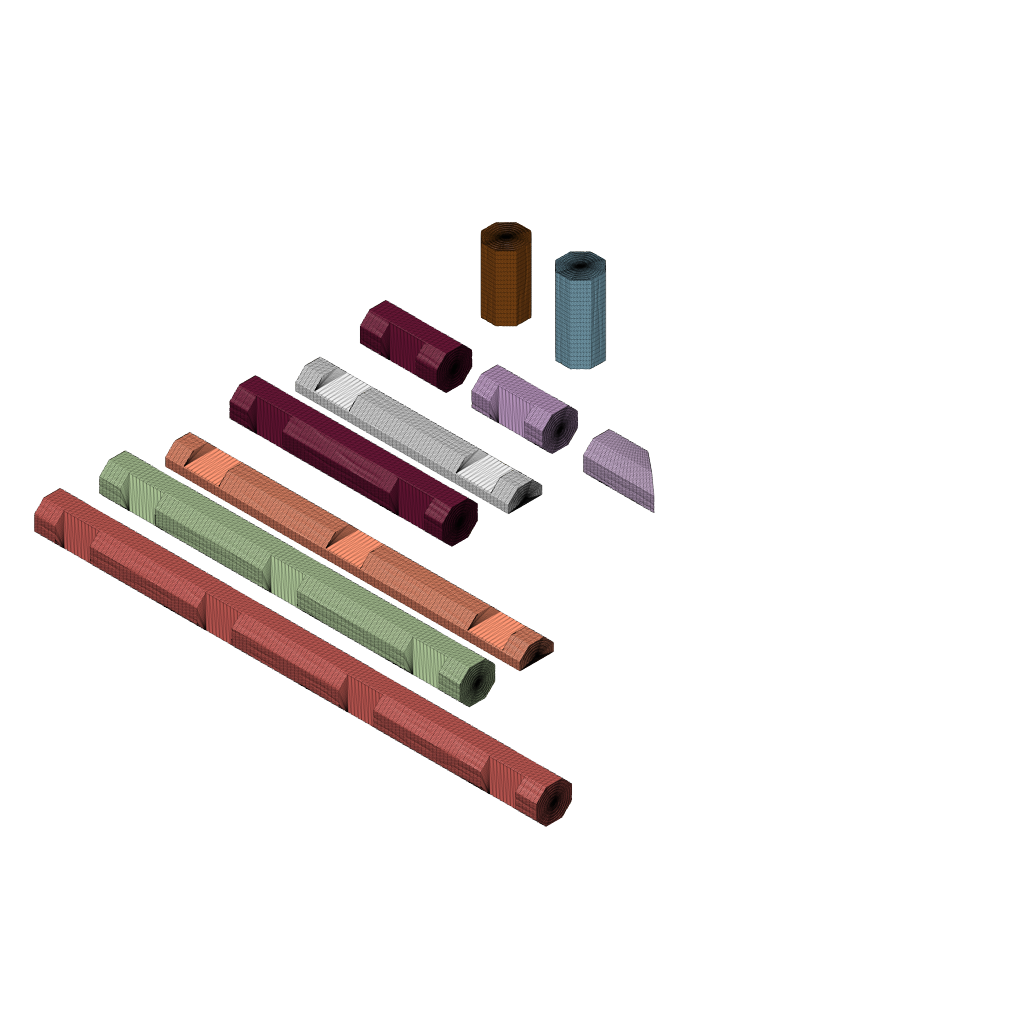
DeadPresidentTreeSections_flat_end_octagonal (Autodesk Fusion 360 design; units mm, degrees)
part number: 2026-11-17-20-53-10-812
part number: 2026-11-17-20-53-11-139
part number: 2026-11-17-20-53-11-399
part number: 2026-11-17-20-53-11-676
part number: 2026-11-17-20-53-11-946
part number: 2026-11-17-20-53-12-259
part number: 2026-11-17-20-53-12-647
part number: 2026-11-17-20-53-13-070
part number: 2026-11-17-20-53-13-551
part number: 2026-11-17-20-53-13-968
part number: 2026-11-17-20-53-14-124
Autodesk Fusion 360 part; units mm, degrees
sketch "Section" plane through (0, 0, 0) normal (1, 0, 0) x (0, 0, -1) in component "log_1insert_1-5_8_oct"
  line L0 (0.4, -9.525) -> (0.4, 9.525)
  line L1 (0.4, 9.525) -> (-18.65, 9.525)
  line L2 (-18.65, 9.525) -> (-18.65, -9.525)
  line L3 (-18.65, -9.525) -> (0.4, -9.525)
  dimension "d14" = 9.525
  dimension "d15" = 0.4
  dimension "d16" = 9.525
  dimension "d17" = 18.65
  constraint vertical L0
  constraint horizontal L1
  constraint vertical L2
  constraint horizontal L3
  measures "d14" vertical distance of origin L0.start
  measures "d15" horizontal distance of origin L0.start
  measures "d16" vertical distance of origin L1.end
  measures "d17" horizontal distance of origin L1.end
extrude "Log" add sketch "Section" along normal blind 41.275 makes body 1 in component "log_1insert_1-5_8_oct"
chamfer "Octagon corners" distance 5.5796 angle 45 4 edges at (20.6375, -9.525, 18.65) (20.6375, 9.525, 18.65) (20.6375, 9.525, -0.4) (20.6375, -9.525, -0.4) tangent chain off on bodies 1 in component "log_1insert_1-5_8_oct"
sketch "Flats" plane through (0, 0, 0) normal (1, 0, 0) x (0, 0, -1) in component "log_1insert_1-5_8_oct"
  line L0 (0.8, -11.525) -> (0.8, 11.525)
  line L1 (0.8, 11.525) -> (0, 11.525)
  line L2 (0, 11.525) -> (0, -11.525)
  line L3 (0, -11.525) -> (0.8, -11.525)
  line L4 (-18.25, -11.525) -> (-18.25, 11.525)
  line L5 (-18.25, 11.525) -> (-20.05, 11.525)
  line L6 (-20.05, 11.525) -> (-20.05, -11.525)
  line L7 (-20.05, -11.525) -> (-18.25, -11.525)
  dimension "d21" = 11.525
  dimension "d22" = 0.8
  dimension "d23" = 11.525
  dimension "d24" = 11.525
  dimension "d25" = 18.25
  dimension "d26" = 11.525
  dimension "d27" = 20.05
  constraint vertical L0
  constraint horizontal L1
  constraint vertical L2
  constraint horizontal L3
  constraint vertical origin L1.end
  constraint vertical L4
  constraint horizontal L5
  constraint vertical L6
  constraint horizontal L7
  measures "d21" vertical distance of origin L0.start
  measures "d22" horizontal distance of origin L0.start
  measures "d23" vertical distance of origin L1.end
  measures "d24" vertical distance of origin L4.start
  measures "d25" horizontal distance of origin L4.start
  measures "d26" vertical distance of origin L5.end
  measures "d27" horizontal distance of origin L5.end
extrude "Flats (1)" cut sketch "Flats" along normal blind 41.275 bodies 1 in component "log_1insert_1-5_8_oct"
sketch "Notch" plane through (0, 0, 0) normal (0, 0, 1) x (1, 0, 0) in component "log_1insert_1-5_8_oct"
  line L0 (11.3125, 4.7625) -> (29.9625, 4.7625)
  line L1 (29.9625, 4.7625) -> (29.9625, 11.525)
  line L2 (29.9625, 11.525) -> (11.3125, 11.525)
  line L3 (11.3125, 11.525) -> (11.3125, 4.7625)
  line L4 (11.3125, -4.7625) -> (29.9625, -4.7625)
  line L5 (29.9625, -4.7625) -> (29.9625, -11.525)
  line L6 (29.9625, -11.525) -> (11.3125, -11.525)
  line L7 (11.3125, -11.525) -> (11.3125, -4.7625)
  dimension "d30" = 11.3125
  dimension "d31" = 4.7625
  dimension "d32" = 29.9625
  dimension "d33" = 11.525
  dimension "d34" = 11.3125
  dimension "d35" = 4.7625
  dimension "d36" = 29.9625
  dimension "d37" = 11.525
  constraint horizontal L0
  constraint vertical L1
  constraint horizontal L2
  constraint vertical L3
  constraint horizontal L4
  constraint vertical L5
  constraint horizontal L6
  constraint vertical L7
  measures "d30" horizontal distance of origin L0.start
  measures "d31" vertical distance of origin L0.start
  measures "d32" horizontal distance of origin L1.end
  measures "d33" vertical distance of origin L1.end
  measures "d34" horizontal distance of origin L4.start
  measures "d35" vertical distance of origin L4.start
  measures "d36" horizontal distance of origin L5.end
  measures "d37" vertical distance of origin L5.end
extrude "Notch cut" cut sketch "Notch" along normal blind 21.05 bodies 1 in component "log_1insert_1-5_8_oct"
pattern_linear "Notch pattern" count 2 spacing 0.001 along (1, 0, 0) count 3 spacing 0 along (1, 0, 0) of "Notch cut" in component "log_1insert_1-5_8_oct"
other "Base Mesh Feature1" in component "log_1insert_1-5_8_oct"
sketch "Section (2)" plane through (0, 0, 0) normal (1, 0, 0) x (0, 0, -1) in component "log_1insert_1-1_2_oct"
  line L0 (0.4, -9.525) -> (0.4, 9.525)
  line L1 (0.4, 9.525) -> (-18.65, 9.525)
  line L2 (-18.65, 9.525) -> (-18.65, -9.525)
  line L3 (-18.65, -9.525) -> (0.4, -9.525)
  dimension "d48" = 9.525
  dimension "d49" = 0.4
  dimension "d50" = 9.525
  dimension "d51" = 18.65
  constraint vertical L0
  constraint horizontal L1
  constraint vertical L2
  constraint horizontal L3
  measures "d48" vertical distance of origin L0.start
  measures "d49" horizontal distance of origin L0.start
  measures "d50" vertical distance of origin L1.end
  measures "d51" horizontal distance of origin L1.end
extrude "Log'" add sketch "Section (2)" along normal blind 38.1 separate body makes body 2 in component "log_1insert_1-1_2_oct"
chamfer "Octagon corners'" distance 5.5796 angle 45 4 edges at (19.05, -9.525, 18.65) (19.05, 9.525, 18.65) (19.05, 9.525, -0.4) (19.05, -9.525, -0.4) tangent chain off on bodies 2 in component "log_1insert_1-1_2_oct"
sketch "Flats (2)" plane through (0, 0, 0) normal (1, 0, 0) x (0, 0, -1) in component "log_1insert_1-1_2_oct"
  line L0 (0.8, -11.525) -> (0.8, 11.525)
  line L1 (0.8, 11.525) -> (0, 11.525)
  line L2 (0, 11.525) -> (0, -11.525)
  line L3 (0, -11.525) -> (0.8, -11.525)
  line L4 (-18.25, -11.525) -> (-18.25, 11.525)
  line L5 (-18.25, 11.525) -> (-20.05, 11.525)
  line L6 (-20.05, 11.525) -> (-20.05, -11.525)
  line L7 (-20.05, -11.525) -> (-18.25, -11.525)
  dimension "d55" = 11.525
  dimension "d56" = 0.8
  dimension "d57" = 11.525
  dimension "d58" = 11.525
  dimension "d59" = 18.25
  dimension "d60" = 11.525
  dimension "d61" = 20.05
  constraint vertical L0
  constraint horizontal L1
  constraint vertical L2
  constraint horizontal L3
  constraint vertical origin L1.end
  constraint vertical L4
  constraint horizontal L5
  constraint vertical L6
  constraint horizontal L7
  measures "d55" vertical distance of origin L0.start
  measures "d56" horizontal distance of origin L0.start
  measures "d57" vertical distance of origin L1.end
  measures "d58" vertical distance of origin L4.start
  measures "d59" horizontal distance of origin L4.start
  measures "d60" vertical distance of origin L5.end
  measures "d61" horizontal distance of origin L5.end
extrude "Flats (1)'" cut sketch "Flats (2)" along normal blind 38.1 bodies 2 in component "log_1insert_1-1_2_oct"
sketch "Notch (2)" plane through (0, 0, 0) normal (0, 0, 1) x (1, 0, 0) in component "log_1insert_1-1_2_oct"
  line L0 (9.725, 4.7625) -> (28.375, 4.7625)
  line L1 (28.375, 4.7625) -> (28.375, 11.525)
  line L2 (28.375, 11.525) -> (9.725, 11.525)
  line L3 (9.725, 11.525) -> (9.725, 4.7625)
  line L4 (9.725, -4.7625) -> (28.375, -4.7625)
  line L5 (28.375, -4.7625) -> (28.375, -11.525)
  line L6 (28.375, -11.525) -> (9.725, -11.525)
  line L7 (9.725, -11.525) -> (9.725, -4.7625)
  dimension "d64" = 9.725
  dimension "d65" = 4.7625
  dimension "d66" = 28.375
  dimension "d67" = 11.525
  dimension "d68" = 9.725
  dimension "d69" = 4.7625
  dimension "d70" = 28.375
  dimension "d71" = 11.525
  constraint horizontal L0
  constraint vertical L1
  constraint horizontal L2
  constraint vertical L3
  constraint horizontal L4
  constraint vertical L5
  constraint horizontal L6
  constraint vertical L7
  measures "d64" horizontal distance of origin L0.start
  measures "d65" vertical distance of origin L0.start
  measures "d66" horizontal distance of origin L1.end
  measures "d67" vertical distance of origin L1.end
  measures "d68" horizontal distance of origin L4.start
  measures "d69" vertical distance of origin L4.start
  measures "d70" horizontal distance of origin L5.end
  measures "d71" vertical distance of origin L5.end
extrude "Notch cut'" cut sketch "Notch (2)" along normal blind 21.05 bodies 2 in component "log_1insert_1-1_2_oct"
pattern_linear "Notch pattern'" count 2 spacing 0.001 along (1, 0, 0) count 3 spacing 0 along (1, 0, 0) of "Notch cut'" in component "log_1insert_1-1_2_oct"
other "Base Mesh Feature1'" in component "log_1insert_1-1_2_oct"
sketch "Section (3)" plane through (0, 0, 0) normal (1, 0, 0) x (0, 0, -1) in component "log_2insert_4-1_2_oct"
  line L0 (0.4, -9.525) -> (0.4, 9.525)
  line L1 (0.4, 9.525) -> (-18.65, 9.525)
  line L2 (-18.65, 9.525) -> (-18.65, -9.525)
  line L3 (-18.65, -9.525) -> (0.4, -9.525)
  dimension "d82" = 9.525
  dimension "d83" = 0.4
  dimension "d84" = 9.525
  dimension "d85" = 18.65
  constraint vertical L0
  constraint horizontal L1
  constraint vertical L2
  constraint horizontal L3
  measures "d82" vertical distance of origin L0.start
  measures "d83" horizontal distance of origin L0.start
  measures "d84" vertical distance of origin L1.end
  measures "d85" horizontal distance of origin L1.end
extrude "Log''" add sketch "Section (3)" along normal blind 114.3 separate body makes body 3 in component "log_2insert_4-1_2_oct"
chamfer "Octagon corners''" distance 5.5796 angle 45 4 edges at (57.15, -9.525, 18.65) (57.15, 9.525, 18.65) (57.15, 9.525, -0.4) (57.15, -9.525, -0.4) tangent chain off on bodies 3 in component "log_2insert_4-1_2_oct"
sketch "Flats (3)" plane through (0, 0, 0) normal (1, 0, 0) x (0, 0, -1) in component "log_2insert_4-1_2_oct"
  line L0 (0.8, -11.525) -> (0.8, 11.525)
  line L1 (0.8, 11.525) -> (0, 11.525)
  line L2 (0, 11.525) -> (0, -11.525)
  line L3 (0, -11.525) -> (0.8, -11.525)
  line L4 (-18.25, -11.525) -> (-18.25, 11.525)
  line L5 (-18.25, 11.525) -> (-20.05, 11.525)
  line L6 (-20.05, 11.525) -> (-20.05, -11.525)
  line L7 (-20.05, -11.525) -> (-18.25, -11.525)
  dimension "d89" = 11.525
  dimension "d90" = 0.8
  dimension "d91" = 11.525
  dimension "d92" = 11.525
  dimension "d93" = 18.25
  dimension "d94" = 11.525
  dimension "d95" = 20.05
  constraint vertical L0
  constraint horizontal L1
  constraint vertical L2
  constraint horizontal L3
  constraint vertical origin L1.end
  constraint vertical L4
  constraint horizontal L5
  constraint vertical L6
  constraint horizontal L7
  measures "d89" vertical distance of origin L0.start
  measures "d90" horizontal distance of origin L0.start
  measures "d91" vertical distance of origin L1.end
  measures "d92" vertical distance of origin L4.start
  measures "d93" horizontal distance of origin L4.start
  measures "d94" vertical distance of origin L5.end
  measures "d95" horizontal distance of origin L5.end
extrude "Flats (1)''" cut sketch "Flats (3)" along normal blind 114.3 bodies 3 in component "log_2insert_4-1_2_oct"
sketch "Notch (3)" plane through (0, 0, 0) normal (0, 0, 1) x (1, 0, 0) in component "log_2insert_4-1_2_oct"
  line L0 (9.725, 4.7625) -> (28.375, 4.7625)
  line L1 (28.375, 4.7625) -> (28.375, 11.525)
  line L2 (28.375, 11.525) -> (9.725, 11.525)
  line L3 (9.725, 11.525) -> (9.725, 4.7625)
  line L4 (9.725, -4.7625) -> (28.375, -4.7625)
  line L5 (28.375, -4.7625) -> (28.375, -11.525)
  line L6 (28.375, -11.525) -> (9.725, -11.525)
  line L7 (9.725, -11.525) -> (9.725, -4.7625)
  dimension "d98" = 9.725
  dimension "d99" = 4.7625
  dimension "d100" = 28.375
  dimension "d101" = 11.525
  dimension "d102" = 9.725
  dimension "d103" = 4.7625
  dimension "d104" = 28.375
  dimension "d105" = 11.525
  constraint horizontal L0
  constraint vertical L1
  constraint horizontal L2
  constraint vertical L3
  constraint horizontal L4
  constraint vertical L5
  constraint horizontal L6
  constraint vertical L7
  measures "d98" horizontal distance of origin L0.start
  measures "d99" vertical distance of origin L0.start
  measures "d100" horizontal distance of origin L1.end
  measures "d101" vertical distance of origin L1.end
  measures "d102" horizontal distance of origin L4.start
  measures "d103" vertical distance of origin L4.start
  measures "d104" horizontal distance of origin L5.end
  measures "d105" vertical distance of origin L5.end
extrude "Notch cut''" cut sketch "Notch (3)" along normal blind 21.05 bodies 3 in component "log_2insert_4-1_2_oct"
pattern_linear "Notch pattern''" count 2 spacing 76.2 along (1, 0, 0) count 3 spacing 0 along (1, 0, 0) of "Notch cut''" in component "log_2insert_4-1_2_oct"
other "Base Mesh Feature1''" in component "log_2insert_4-1_2_oct"
sketch "Section (4)" plane through (0, 0, 0) normal (1, 0, 0) x (0, 0, -1) in component "log_3insert_7-5_8_oct"
  line L0 (0.4, -9.525) -> (0.4, 9.525)
  line L1 (0.4, 9.525) -> (-18.65, 9.525)
  line L2 (-18.65, 9.525) -> (-18.65, -9.525)
  line L3 (-18.65, -9.525) -> (0.4, -9.525)
  dimension "d116" = 9.525
  dimension "d117" = 0.4
  dimension "d118" = 9.525
  dimension "d119" = 18.65
  constraint vertical L0
  constraint horizontal L1
  constraint vertical L2
  constraint horizontal L3
  measures "d116" vertical distance of origin L0.start
  measures "d117" horizontal distance of origin L0.start
  measures "d118" vertical distance of origin L1.end
  measures "d119" horizontal distance of origin L1.end
extrude "Log'''" add sketch "Section (4)" along normal blind 193.675 separate body makes body 4 in component "log_3insert_7-5_8_oct"
chamfer "Octagon corners'''" distance 5.5796 angle 45 4 edges at (96.8375, -9.525, 18.65) (96.8375, 9.525, 18.65) (96.8375, 9.525, -0.4) (96.8375, -9.525, -0.4) tangent chain off on bodies 4 in component "log_3insert_7-5_8_oct"
sketch "Flats (4)" plane through (0, 0, 0) normal (1, 0, 0) x (0, 0, -1) in component "log_3insert_7-5_8_oct"
  line L0 (0.8, -11.525) -> (0.8, 11.525)
  line L1 (0.8, 11.525) -> (0, 11.525)
  line L2 (0, 11.525) -> (0, -11.525)
  line L3 (0, -11.525) -> (0.8, -11.525)
  line L4 (-18.25, -11.525) -> (-18.25, 11.525)
  line L5 (-18.25, 11.525) -> (-20.05, 11.525)
  line L6 (-20.05, 11.525) -> (-20.05, -11.525)
  line L7 (-20.05, -11.525) -> (-18.25, -11.525)
  dimension "d123" = 11.525
  dimension "d124" = 0.8
  dimension "d125" = 11.525
  dimension "d126" = 11.525
  dimension "d127" = 18.25
  dimension "d128" = 11.525
  dimension "d129" = 20.05
  constraint vertical L0
  constraint horizontal L1
  constraint vertical L2
  constraint horizontal L3
  constraint vertical origin L1.end
  constraint vertical L4
  constraint horizontal L5
  constraint vertical L6
  constraint horizontal L7
  measures "d123" vertical distance of origin L0.start
  measures "d124" horizontal distance of origin L0.start
  measures "d125" vertical distance of origin L1.end
  measures "d126" vertical distance of origin L4.start
  measures "d127" horizontal distance of origin L4.start
  measures "d128" vertical distance of origin L5.end
  measures "d129" horizontal distance of origin L5.end
extrude "Flats (1)'''" cut sketch "Flats (4)" along normal blind 193.675 bodies 4 in component "log_3insert_7-5_8_oct"
sketch "Notch (4)" plane through (0, 0, 0) normal (0, 0, 1) x (1, 0, 0) in component "log_3insert_7-5_8_oct"
  line L0 (11.3125, 4.7625) -> (29.9625, 4.7625)
  line L1 (29.9625, 4.7625) -> (29.9625, 11.525)
  line L2 (29.9625, 11.525) -> (11.3125, 11.525)
  line L3 (11.3125, 11.525) -> (11.3125, 4.7625)
  line L4 (11.3125, -4.7625) -> (29.9625, -4.7625)
  line L5 (29.9625, -4.7625) -> (29.9625, -11.525)
  line L6 (29.9625, -11.525) -> (11.3125, -11.525)
  line L7 (11.3125, -11.525) -> (11.3125, -4.7625)
  dimension "d132" = 11.3125
  dimension "d133" = 4.7625
  dimension "d134" = 29.9625
  dimension "d135" = 11.525
  dimension "d136" = 11.3125
  dimension "d137" = 4.7625
  dimension "d138" = 29.9625
  dimension "d139" = 11.525
  constraint horizontal L0
  constraint vertical L1
  constraint horizontal L2
  constraint vertical L3
  constraint horizontal L4
  constraint vertical L5
  constraint horizontal L6
  constraint vertical L7
  measures "d132" horizontal distance of origin L0.start
  measures "d133" vertical distance of origin L0.start
  measures "d134" horizontal distance of origin L1.end
  measures "d135" vertical distance of origin L1.end
  measures "d136" horizontal distance of origin L4.start
  measures "d137" vertical distance of origin L4.start
  measures "d138" horizontal distance of origin L5.end
  measures "d139" vertical distance of origin L5.end
extrude "Notch cut'''" cut sketch "Notch (4)" along normal blind 21.05 bodies 4 in component "log_3insert_7-5_8_oct"
pattern_linear "Notch pattern'''" count 3 spacing 76.2 along (1, 0, 0) count 3 spacing 0 along (1, 0, 0) of "Notch cut'''" in component "log_3insert_7-5_8_oct"
other "Base Mesh Feature1'''" in component "log_3insert_7-5_8_oct"
sketch "Section (5)" plane through (0, 0, 0) normal (1, 0, 0) x (0, 0, -1) in component "log_4insert_10-5_8_oct"
  line L0 (0.4, -9.525) -> (0.4, 9.525)
  line L1 (0.4, 9.525) -> (-18.65, 9.525)
  line L2 (-18.65, 9.525) -> (-18.65, -9.525)
  line L3 (-18.65, -9.525) -> (0.4, -9.525)
  dimension "d150" = 9.525
  dimension "d151" = 0.4
  dimension "d152" = 9.525
  dimension "d153" = 18.65
  constraint vertical L0
  constraint horizontal L1
  constraint vertical L2
  constraint horizontal L3
  measures "d150" vertical distance of origin L0.start
  measures "d151" horizontal distance of origin L0.start
  measures "d152" vertical distance of origin L1.end
  measures "d153" horizontal distance of origin L1.end
extrude "Log''''" add sketch "Section (5)" along normal blind 269.875 separate body makes body 5 in component "log_4insert_10-5_8_oct"
chamfer "Octagon corners''''" distance 5.5796 angle 45 4 edges at (134.9375, -9.525, 18.65) (134.9375, 9.525, 18.65) (134.9375, 9.525, -0.4) (134.9375, -9.525, -0.4) tangent chain off on bodies 5 in component "log_4insert_10-5_8_oct"
sketch "Flats (5)" plane through (0, 0, 0) normal (1, 0, 0) x (0, 0, -1) in component "log_4insert_10-5_8_oct"
  line L0 (0.8, -11.525) -> (0.8, 11.525)
  line L1 (0.8, 11.525) -> (0, 11.525)
  line L2 (0, 11.525) -> (0, -11.525)
  line L3 (0, -11.525) -> (0.8, -11.525)
  line L4 (-18.25, -11.525) -> (-18.25, 11.525)
  line L5 (-18.25, 11.525) -> (-20.05, 11.525)
  line L6 (-20.05, 11.525) -> (-20.05, -11.525)
  line L7 (-20.05, -11.525) -> (-18.25, -11.525)
  dimension "d157" = 11.525
  dimension "d158" = 0.8
  dimension "d159" = 11.525
  dimension "d160" = 11.525
  dimension "d161" = 18.25
  dimension "d162" = 11.525
  dimension "d163" = 20.05
  constraint vertical L0
  constraint horizontal L1
  constraint vertical L2
  constraint horizontal L3
  constraint vertical origin L1.end
  constraint vertical L4
  constraint horizontal L5
  constraint vertical L6
  constraint horizontal L7
  measures "d157" vertical distance of origin L0.start
  measures "d158" horizontal distance of origin L0.start
  measures "d159" vertical distance of origin L1.end
  measures "d160" vertical distance of origin L4.start
  measures "d161" horizontal distance of origin L4.start
  measures "d162" vertical distance of origin L5.end
  measures "d163" horizontal distance of origin L5.end
extrude "Flats (1)''''" cut sketch "Flats (5)" along normal blind 269.875 bodies 5 in component "log_4insert_10-5_8_oct"
sketch "Notch (5)" plane through (0, 0, 0) normal (0, 0, 1) x (1, 0, 0) in component "log_4insert_10-5_8_oct"
  line L0 (11.3125, 4.7625) -> (29.9625, 4.7625)
  line L1 (29.9625, 4.7625) -> (29.9625, 11.525)
  line L2 (29.9625, 11.525) -> (11.3125, 11.525)
  line L3 (11.3125, 11.525) -> (11.3125, 4.7625)
  line L4 (11.3125, -4.7625) -> (29.9625, -4.7625)
  line L5 (29.9625, -4.7625) -> (29.9625, -11.525)
  line L6 (29.9625, -11.525) -> (11.3125, -11.525)
  line L7 (11.3125, -11.525) -> (11.3125, -4.7625)
  dimension "d166" = 11.3125
  dimension "d167" = 4.7625
  dimension "d168" = 29.9625
  dimension "d169" = 11.525
  dimension "d170" = 11.3125
  dimension "d171" = 4.7625
  dimension "d172" = 29.9625
  dimension "d173" = 11.525
  constraint horizontal L0
  constraint vertical L1
  constraint horizontal L2
  constraint vertical L3
  constraint horizontal L4
  constraint vertical L5
  constraint horizontal L6
  constraint vertical L7
  measures "d166" horizontal distance of origin L0.start
  measures "d167" vertical distance of origin L0.start
  measures "d168" horizontal distance of origin L1.end
  measures "d169" vertical distance of origin L1.end
  measures "d170" horizontal distance of origin L4.start
  measures "d171" vertical distance of origin L4.start
  measures "d172" horizontal distance of origin L5.end
  measures "d173" vertical distance of origin L5.end
extrude "Notch cut''''" cut sketch "Notch (5)" along normal blind 21.05 bodies 5 in component "log_4insert_10-5_8_oct"
pattern_linear "Notch pattern''''" count 4 spacing 76.2 along (1, 0, 0) count 3 spacing 0 along (1, 0, 0) of "Notch cut''''" in component "log_4insert_10-5_8_oct"
other "Base Mesh Feature1''''" in component "log_4insert_10-5_8_oct"
sketch "Section (6)" plane through (0, 0, 0) normal (1, 0, 0) x (0, 0, -1) in component "base_log_4-1_2_oct"
  line L0 (9.525, -9.525) -> (9.525, 9.525)
  line L1 (9.525, 9.525) -> (-9.525, 9.525)
  line L2 (-9.525, 9.525) -> (-9.525, -9.525)
  line L3 (-9.525, -9.525) -> (9.525, -9.525)
  dimension "d184" = 9.525
  dimension "d185" = 9.525
  dimension "d186" = 9.525
  dimension "d187" = 9.525
  constraint vertical L0
  constraint horizontal L1
  constraint vertical L2
  constraint horizontal L3
  measures "d184" vertical distance of origin L0.start
  measures "d185" horizontal distance of origin L0.start
  measures "d186" vertical distance of origin L1.end
  measures "d187" horizontal distance of origin L1.end
extrude "Log'''''" add sketch "Section (6)" along normal blind 114.3 separate body makes body 6 in component "base_log_4-1_2_oct"
chamfer "Octagon corners'''''" distance 5.5796 angle 45 4 edges at (57.15, -9.525, 9.525) (57.15, 9.525, 9.525) (57.15, 9.525, -9.525) (57.15, -9.525, -9.525) tangent chain off on bodies 6 in component "base_log_4-1_2_oct"
sketch "Bed and side flats" plane through (0, 0, 0) normal (1, 0, 0) x (0, 0, -1) in component "base_log_4-1_2_oct"
  line L0 (10.525, -11.525) -> (10.525, 11.525)
  line L1 (10.525, 11.525) -> (0, 11.525)
  line L2 (0, 11.525) -> (0, -11.525)
  line L3 (0, -11.525) -> (10.525, -11.525)
  line L4 (1, 9.125) -> (1, 11.525)
  line L5 (1, 11.525) -> (-20.05, 11.525)
  line L6 (-20.05, 11.525) -> (-20.05, 9.125)
  line L7 (-20.05, 9.125) -> (1, 9.125)
  line L8 (1, -9.125) -> (1, -11.525)
  line L9 (1, -11.525) -> (-20.05, -11.525)
  line L10 (-20.05, -11.525) -> (-20.05, -9.125)
  line L11 (-20.05, -9.125) -> (1, -9.125)
  dimension "d191" = 11.525
  dimension "d192" = 10.525
  dimension "d193" = 11.525
  dimension "d194" = 9.125
  dimension "d195" = 1
  dimension "d196" = 11.525
  dimension "d197" = 20.05
  dimension "d198" = 9.125
  dimension "d199" = 1
  dimension "d200" = 11.525
  dimension "d201" = 20.05
  constraint vertical L0
  constraint horizontal L1
  constraint vertical L2
  constraint horizontal L3
  constraint vertical origin L1.end
  constraint vertical L4
  constraint horizontal L5
  constraint vertical L6
  constraint horizontal L7
  constraint vertical L8
  constraint horizontal L9
  constraint vertical L10
  constraint horizontal L11
  measures "d191" vertical distance of origin L0.start
  measures "d192" horizontal distance of origin L0.start
  measures "d193" vertical distance of origin L1.end
  measures "d194" vertical distance of origin L4.start
  measures "d195" horizontal distance of origin L4.start
  measures "d196" vertical distance of origin L5.end
  measures "d197" horizontal distance of origin L5.end
  measures "d198" vertical distance of origin L8.start
  measures "d199" horizontal distance of origin L8.start
  measures "d200" vertical distance of origin L9.end
  measures "d201" horizontal distance of origin L9.end
extrude "Bed and side flats (1)" cut sketch "Bed and side flats" along normal blind 114.3 bodies 6 in component "base_log_4-1_2_oct"
sketch "Notch (6)" plane through (0, 0, 0) normal (0, 1, 0) x (1, 0, 0) in component "base_log_4-1_2_oct"
  line L0 (9.725, -4.7625) -> (28.375, -4.7625)
  line L1 (28.375, -4.7625) -> (28.375, -10.525)
  line L2 (28.375, -10.525) -> (9.725, -10.525)
  line L3 (9.725, -10.525) -> (9.725, -4.7625)
  dimension "d204" = 9.725
  dimension "d205" = 4.7625
  dimension "d206" = 28.375
  dimension "d207" = 10.525
  constraint horizontal L0
  constraint vertical L1
  constraint horizontal L2
  constraint vertical L3
  measures "d204" horizontal distance of origin L0.start
  measures "d205" vertical distance of origin L0.start
  measures "d206" horizontal distance of origin L1.end
  measures "d207" vertical distance of origin L1.end
extrude "Notch cut'''''" cut sketch "Notch (6)" along normal mid plane 21.05 bodies 6 in component "base_log_4-1_2_oct"
pattern_linear "Notch pattern'''''" count 2 spacing 76.2 along (1, 0, 0) count 3 spacing 0 along (1, 0, 0) of "Notch cut'''''" in component "base_log_4-1_2_oct"
other "Base Mesh Feature1'''''" in component "base_log_4-1_2_oct"
sketch "Section (7)" plane through (0, 0, 0) normal (1, 0, 0) x (0, 0, -1) in component "base_log_7-1_2_oct"
  line L0 (9.525, -9.525) -> (9.525, 9.525)
  line L1 (9.525, 9.525) -> (-9.525, 9.525)
  line L2 (-9.525, 9.525) -> (-9.525, -9.525)
  line L3 (-9.525, -9.525) -> (9.525, -9.525)
  dimension "d218" = 9.525
  dimension "d219" = 9.525
  dimension "d220" = 9.525
  dimension "d221" = 9.525
  constraint vertical L0
  constraint horizontal L1
  constraint vertical L2
  constraint horizontal L3
  measures "d218" vertical distance of origin L0.start
  measures "d219" horizontal distance of origin L0.start
  measures "d220" vertical distance of origin L1.end
  measures "d221" horizontal distance of origin L1.end
extrude "Log''''''" add sketch "Section (7)" along normal blind 190.5 separate body makes body 7 in component "base_log_7-1_2_oct"
chamfer "Octagon corners''''''" distance 5.5796 angle 45 4 edges at (95.25, -9.525, 9.525) (95.25, 9.525, 9.525) (95.25, 9.525, -9.525) (95.25, -9.525, -9.525) tangent chain off on bodies 7 in component "base_log_7-1_2_oct"
sketch "Bed and side flats (2)" plane through (0, 0, 0) normal (1, 0, 0) x (0, 0, -1) in component "base_log_7-1_2_oct"
  line L0 (10.525, -11.525) -> (10.525, 11.525)
  line L1 (10.525, 11.525) -> (0, 11.525)
  line L2 (0, 11.525) -> (0, -11.525)
  line L3 (0, -11.525) -> (10.525, -11.525)
  line L4 (1, 9.125) -> (1, 11.525)
  line L5 (1, 11.525) -> (-20.05, 11.525)
  line L6 (-20.05, 11.525) -> (-20.05, 9.125)
  line L7 (-20.05, 9.125) -> (1, 9.125)
  line L8 (1, -9.125) -> (1, -11.525)
  line L9 (1, -11.525) -> (-20.05, -11.525)
  line L10 (-20.05, -11.525) -> (-20.05, -9.125)
  line L11 (-20.05, -9.125) -> (1, -9.125)
  dimension "d225" = 11.525
  dimension "d226" = 10.525
  dimension "d227" = 11.525
  dimension "d228" = 9.125
  dimension "d229" = 1
  dimension "d230" = 11.525
  dimension "d231" = 20.05
  dimension "d232" = 9.125
  dimension "d233" = 1
  dimension "d234" = 11.525
  dimension "d235" = 20.05
  constraint vertical L0
  constraint horizontal L1
  constraint vertical L2
  constraint horizontal L3
  constraint vertical origin L1.end
  constraint vertical L4
  constraint horizontal L5
  constraint vertical L6
  constraint horizontal L7
  constraint vertical L8
  constraint horizontal L9
  constraint vertical L10
  constraint horizontal L11
  measures "d225" vertical distance of origin L0.start
  measures "d226" horizontal distance of origin L0.start
  measures "d227" vertical distance of origin L1.end
  measures "d228" vertical distance of origin L4.start
  measures "d229" horizontal distance of origin L4.start
  measures "d230" vertical distance of origin L5.end
  measures "d231" horizontal distance of origin L5.end
  measures "d232" vertical distance of origin L8.start
  measures "d233" horizontal distance of origin L8.start
  measures "d234" vertical distance of origin L9.end
  measures "d235" horizontal distance of origin L9.end
extrude "Bed and side flats (1)'" cut sketch "Bed and side flats (2)" along normal blind 190.5 bodies 7 in component "base_log_7-1_2_oct"
sketch "Notch (7)" plane through (0, 0, 0) normal (0, 1, 0) x (1, 0, 0) in component "base_log_7-1_2_oct"
  line L0 (9.725, -4.7625) -> (28.375, -4.7625)
  line L1 (28.375, -4.7625) -> (28.375, -10.525)
  line L2 (28.375, -10.525) -> (9.725, -10.525)
  line L3 (9.725, -10.525) -> (9.725, -4.7625)
  dimension "d238" = 9.725
  dimension "d239" = 4.7625
  dimension "d240" = 28.375
  dimension "d241" = 10.525
  constraint horizontal L0
  constraint vertical L1
  constraint horizontal L2
  constraint vertical L3
  measures "d238" horizontal distance of origin L0.start
  measures "d239" vertical distance of origin L0.start
  measures "d240" horizontal distance of origin L1.end
  measures "d241" vertical distance of origin L1.end
extrude "Notch cut''''''" cut sketch "Notch (7)" along normal mid plane 21.05 bodies 7 in component "base_log_7-1_2_oct"
pattern_linear "Notch pattern''''''" count 3 spacing 76.2 along (1, 0, 0) count 3 spacing 0 along (1, 0, 0) of "Notch cut''''''" in component "base_log_7-1_2_oct"
other "Base Mesh Feature1''''''" in component "base_log_7-1_2_oct"
sketch "Section (8)" plane through (0, 0, 0) normal (1, 0, 0) x (0, 0, -1) in component "beveled_end_1-1_2_oct"
  line L0 (0.4, -9.525) -> (0.4, 9.525)
  line L1 (0.4, 9.525) -> (-18.65, 9.525)
  line L2 (-18.65, 9.525) -> (-18.65, -9.525)
  line L3 (-18.65, -9.525) -> (0.4, -9.525)
  dimension "d250" = 9.525
  dimension "d251" = 0.4
  dimension "d252" = 9.525
  dimension "d253" = 18.65
  constraint vertical L0
  constraint horizontal L1
  constraint vertical L2
  constraint horizontal L3
  measures "d250" vertical distance of origin L0.start
  measures "d251" horizontal distance of origin L0.start
  measures "d252" vertical distance of origin L1.end
  measures "d253" horizontal distance of origin L1.end
extrude "Log'''''''" add sketch "Section (8)" along normal blind 38.1 separate body makes body 8 in component "beveled_end_1-1_2_oct"
chamfer "Octagon corners'''''''" distance 5.5796 angle 45 4 edges at (19.05, -9.525, 18.65) (19.05, 9.525, 18.65) (19.05, 9.525, -0.4) (19.05, -9.525, -0.4) tangent chain off on bodies 8 in component "beveled_end_1-1_2_oct"
sketch "Flats (6)" plane through (0, 0, 0) normal (1, 0, 0) x (0, 0, -1) in component "beveled_end_1-1_2_oct"
  line L0 (0.8, -11.525) -> (0.8, 11.525)
  line L1 (0.8, 11.525) -> (0, 11.525)
  line L2 (0, 11.525) -> (0, -11.525)
  line L3 (0, -11.525) -> (0.8, -11.525)
  line L4 (-18.25, -11.525) -> (-18.25, 11.525)
  line L5 (-18.25, 11.525) -> (-20.05, 11.525)
  line L6 (-20.05, 11.525) -> (-20.05, -11.525)
  line L7 (-20.05, -11.525) -> (-18.25, -11.525)
  dimension "d257" = 11.525
  dimension "d258" = 0.8
  dimension "d259" = 11.525
  dimension "d260" = 11.525
  dimension "d261" = 18.25
  dimension "d262" = 11.525
  dimension "d263" = 20.05
  constraint vertical L0
  constraint horizontal L1
  constraint vertical L2
  constraint horizontal L3
  constraint vertical origin L1.end
  constraint vertical L4
  constraint horizontal L5
  constraint vertical L6
  constraint horizontal L7
  measures "d257" vertical distance of origin L0.start
  measures "d258" horizontal distance of origin L0.start
  measures "d259" vertical distance of origin L1.end
  measures "d260" vertical distance of origin L4.start
  measures "d261" horizontal distance of origin L4.start
  measures "d262" vertical distance of origin L5.end
  measures "d263" horizontal distance of origin L5.end
extrude "Flats (1)'''''" cut sketch "Flats (6)" along normal blind 38.1 bodies 8 in component "beveled_end_1-1_2_oct"
sketch "Slant" plane through (0, 0, 0) normal (0, 0, 1) x (1, 0, 0) in component "beveled_end_1-1_2_oct"
  line L0 (38.1, -9.525) -> (38.1, 9.525)
  line L1 (38.1, 9.525) -> (14.5752, 9.525)
  line L2 (14.5752, 9.525) -> (38.1, -9.525)
  dimension "d266" = 38.1
  dimension "d267" = 9.525
  dimension "d268" = 9.525
  dimension "d269" = 14.5752
  constraint vertical L0.start L0.end
  constraint horizontal L0.end L1.end
  measures "d266" horizontal distance of origin L0.start
  measures "d267" vertical distance of origin L0.start
  measures "d268" vertical distance of origin L0.end
  measures "d269" horizontal distance of origin L1.end
extrude "Slanted end" cut sketch "Slant" along normal blind 21.05 bodies 8 in component "beveled_end_1-1_2_oct"
other "Base Mesh Feature1'''''''" in component "beveled_end_1-1_2_oct"
sketch "Section (9)" plane through (0, 0, 0) normal (0, 0, 1) x (1, 0, 0) in component "solid_log_1-3_8_oct"
  line L0 (0, 0) -> (19.05, 0)
  line L1 (19.05, 0) -> (19.05, 19.05)
  line L2 (19.05, 19.05) -> (0, 19.05)
  line L3 (0, 19.05) -> (0, 0)
  dimension "d273" = 19.05
  dimension "d274" = 19.05
  constraint horizontal L0
  constraint vertical L1
  constraint horizontal L2
  constraint vertical L3
  constraint coincident L0.start L3.end
  measures "d273" horizontal distance of L0.start L1.end
  measures "d274" vertical distance of L0.start L1.end
extrude "Log''''''''" add sketch "Section (9)" along normal blind 34.925 separate body makes body 9 in component "solid_log_1-3_8_oct"
chamfer "Octagon corners''''''''" distance 5.5796 angle 45 4 edges at (0, 19.05, 17.4625) (19.05, 19.05, 17.4625) (19.05, 0, 17.4625) (0, 0, 17.4625) tangent chain off on bodies 9 in component "solid_log_1-3_8_oct"
other "Base Mesh Feature1''''''''" in component "solid_log_1-3_8_oct"
sketch "Section (10)" plane through (0, 0, 0) normal (0, 0, 1) x (1, 0, 0) in component "solid_log_1-5_8_oct"
  line L0 (0, 0) -> (19.05, 0)
  line L1 (19.05, 0) -> (19.05, 19.05)
  line L2 (19.05, 19.05) -> (0, 19.05)
  line L3 (0, 19.05) -> (0, 0)
  dimension "d279" = 19.05
  dimension "d280" = 19.05
  constraint horizontal L0
  constraint vertical L1
  constraint horizontal L2
  constraint vertical L3
  constraint coincident L0.start L3.end
  measures "d279" horizontal distance of L0.start L1.end
  measures "d280" vertical distance of L0.start L1.end
extrude "Log'''''''''" add sketch "Section (10)" along normal blind 41.275 separate body makes body 10 in component "solid_log_1-5_8_oct"
chamfer "Octagon corners'''''''''" distance 5.5796 angle 45 4 edges at (0, 19.05, 20.6375) (19.05, 19.05, 20.6375) (19.05, 0, 20.6375) (0, 0, 20.6375) tangent chain off on bodies 10 in component "solid_log_1-5_8_oct"
other "Base Mesh Feature1'''''''''" in component "solid_log_1-5_8_oct"
component "log_1insert_1-5_8_oct" placed x (1, 0, 0) y (0, 1, 0) z (0, 0, 1) at (0, 175, 0)
component "log_1insert_1-1_2_oct" placed x (1, 0, 0) y (0, 1, 0) z (0, 0, 1) at (60, 175, 0)
component "log_2insert_4-1_2_oct" placed x (1, 0, 0) y (0, 1, 0) z (0, 0, 1) at (0, 105, 0)
component "log_3insert_7-5_8_oct" placed x (1, 0, 0) y (0, 1, 0) z (0, 0, 1) at (0, 35, 0)
component "log_4insert_10-5_8_oct" placed x (1, 0, 0) y (0, 1, 0) z (0, 0, 1) at (0, 0, 0)
component "base_log_4-1_2_oct" placed x (1, 0, 0) y (0, 1, 0) z (0, 0, 1) at (0, 140, 0)
component "base_log_7-1_2_oct" placed x (1, 0, 0) y (0, 1, 0) z (0, 0, 1) at (0, 70, 0)
component "beveled_end_1-1_2_oct" placed x (1, 0, 0) y (0, 1, 0) z (0, 0, 1) at (120, 175, 0)
component "solid_log_1-3_8_oct" placed x (1, 0, 0) y (0, 1, 0) z (0, 0, 1) at (10, 215, 0)
component "solid_log_1-5_8_oct" placed x (1, 0, 0) y (0, 1, 0) z (0, 0, 1) at (50, 215, 0)
hidden bodies 1 2 3 4 5 6 7 8 9 10
equation "LogDia = 0.75 in" comment "Log diameter (across the flats of an octagonal log)"
equation "NotchDepth = 0.1875 in" comment "Notch depth, each side of a log"
equation "NotchCenters = 3 in" comment "Spacing between notch centres"
equation "Clearance = 0.2 mm" comment "Fit clearance per side. Try 0.3 mm for PETG"
equation "PrintFlat = 0.8 mm" comment "Total width taken off a log, as an equal flat on each side; one is the bed side"
equation "MateWidth = LogDia - PrintFlat" comment "Width of a log, base log or gable where it sits in a notch"
equation "NotchWidth = MateWidth + 2 * Clearance" comment "Notch width (mating width plus clearance on each side)"
equation "CourseRise = LogDia - 2 * NotchDepth" comment "Height gained per crossing course"
equation "BaseLogHeight = LogDia / 2" comment "Base-log height (a log split in half along its axis)"
equation "L1a_Length = 1.625 in" comment "Overall length"
equation "L1a_Notches = 1" comment "Number of notch positions"
equation "L1a_FirstNotch = ( L1a_Length - ( L1a_Notches - 1 ) * NotchCenters ) / 2" comment "Centre of the first notch (keeps the row of notches centred)"
equation "L1a_NotchStep = NotchCenters * min(1; L1a_Notches - 1) + 0.001 mm * ( 1 - min(1; L1a_Notches - 1) )" comment "Pattern step: NotchCenters, or about zero when there is only one notch"
equation "d14 = LogDia / 2"
equation "d15 = PrintFlat / 2"
equation "d16 = LogDia / 2"
equation "d17 = LogDia / 2 - PrintFlat / 2 + LogDia / 2"
equation "d18 = L1a_Length"
equation "d20 = LogDia * ( 1 - sqrt(2) / 2 )"
equation "d21 = LogDia / 2 + 2 mm"
equation "d22 = PrintFlat"
equation "d23 = LogDia / 2 + 2 mm"
equation "d24 = LogDia / 2 + 2 mm"
equation "d25 = MateWidth"
equation "d26 = LogDia / 2 + 2 mm"
equation "d27 = LogDia + 1 mm"
equation "d28 = L1a_Length"
equation "d30 = L1a_FirstNotch - NotchWidth / 2"
equation "d31 = LogDia / 2 - NotchDepth"
equation "d32 = L1a_FirstNotch + NotchWidth / 2"
equation "d33 = LogDia / 2 + 2 mm"
equation "d34 = L1a_FirstNotch - NotchWidth / 2"
equation "d35 = LogDia / 2 - NotchDepth"
equation "d36 = L1a_FirstNotch + NotchWidth / 2"
equation "d37 = LogDia / 2 + 2 mm"
equation "d38 = LogDia + 2 mm"
equation "d40 = max(L1a_Notches; 2)"
equation "d42 = L1a_NotchStep"
equation "L1b_Length = 1.5 in" comment "Overall length"
equation "L1b_Notches = 1" comment "Number of notch positions"
equation "L1b_FirstNotch = ( L1b_Length - ( L1b_Notches - 1 ) * NotchCenters ) / 2" comment "Centre of the first notch (keeps the row of notches centred)"
equation "L1b_NotchStep = NotchCenters * min(1; L1b_Notches - 1) + 0.001 mm * ( 1 - min(1; L1b_Notches - 1) )" comment "Pattern step: NotchCenters, or about zero when there is only one notch"
equation "d48 = LogDia / 2"
equation "d49 = PrintFlat / 2"
equation "d50 = LogDia / 2"
equation "d51 = LogDia / 2 - PrintFlat / 2 + LogDia / 2"
equation "d52 = L1b_Length"
equation "d54 = LogDia * ( 1 - sqrt(2) / 2 )"
equation "d55 = LogDia / 2 + 2 mm"
equation "d56 = PrintFlat"
equation "d57 = LogDia / 2 + 2 mm"
equation "d58 = LogDia / 2 + 2 mm"
equation "d59 = MateWidth"
equation "d60 = LogDia / 2 + 2 mm"
equation "d61 = LogDia + 1 mm"
equation "d62 = L1b_Length"
equation "d64 = L1b_FirstNotch - NotchWidth / 2"
equation "d65 = LogDia / 2 - NotchDepth"
equation "d66 = L1b_FirstNotch + NotchWidth / 2"
equation "d67 = LogDia / 2 + 2 mm"
equation "d68 = L1b_FirstNotch - NotchWidth / 2"
equation "d69 = LogDia / 2 - NotchDepth"
equation "d70 = L1b_FirstNotch + NotchWidth / 2"
equation "d71 = LogDia / 2 + 2 mm"
equation "d72 = LogDia + 2 mm"
equation "d74 = max(L1b_Notches; 2)"
equation "d76 = L1b_NotchStep"
equation "L2_Length = 4.5 in" comment "Overall length"
equation "L2_Notches = 2" comment "Number of notch positions"
equation "L2_FirstNotch = ( L2_Length - ( L2_Notches - 1 ) * NotchCenters ) / 2" comment "Centre of the first notch (keeps the row of notches centred)"
equation "L2_NotchStep = NotchCenters * min(1; L2_Notches - 1) + 0.001 mm * ( 1 - min(1; L2_Notches - 1) )" comment "Pattern step: NotchCenters, or about zero when there is only one notch"
equation "d82 = LogDia / 2"
equation "d83 = PrintFlat / 2"
equation "d84 = LogDia / 2"
equation "d85 = LogDia / 2 - PrintFlat / 2 + LogDia / 2"
equation "d86 = L2_Length"
equation "d88 = LogDia * ( 1 - sqrt(2) / 2 )"
equation "d89 = LogDia / 2 + 2 mm"
equation "d90 = PrintFlat"
equation "d91 = LogDia / 2 + 2 mm"
equation "d92 = LogDia / 2 + 2 mm"
equation "d93 = MateWidth"
equation "d94 = LogDia / 2 + 2 mm"
equation "d95 = LogDia + 1 mm"
equation "d96 = L2_Length"
equation "d98 = L2_FirstNotch - NotchWidth / 2"
equation "d99 = LogDia / 2 - NotchDepth"
equation "d100 = L2_FirstNotch + NotchWidth / 2"
equation "d101 = LogDia / 2 + 2 mm"
equation "d102 = L2_FirstNotch - NotchWidth / 2"
equation "d103 = LogDia / 2 - NotchDepth"
equation "d104 = L2_FirstNotch + NotchWidth / 2"
equation "d105 = LogDia / 2 + 2 mm"
equation "d106 = LogDia + 2 mm"
equation "d108 = max(L2_Notches; 2)"
equation "d110 = L2_NotchStep"
equation "L3_Length = 7.625 in" comment "Overall length"
equation "L3_Notches = 3" comment "Number of notch positions"
equation "L3_FirstNotch = ( L3_Length - ( L3_Notches - 1 ) * NotchCenters ) / 2" comment "Centre of the first notch (keeps the row of notches centred)"
equation "L3_NotchStep = NotchCenters * min(1; L3_Notches - 1) + 0.001 mm * ( 1 - min(1; L3_Notches - 1) )" comment "Pattern step: NotchCenters, or about zero when there is only one notch"
equation "d116 = LogDia / 2"
equation "d117 = PrintFlat / 2"
equation "d118 = LogDia / 2"
equation "d119 = LogDia / 2 - PrintFlat / 2 + LogDia / 2"
equation "d120 = L3_Length"
equation "d122 = LogDia * ( 1 - sqrt(2) / 2 )"
equation "d123 = LogDia / 2 + 2 mm"
equation "d124 = PrintFlat"
equation "d125 = LogDia / 2 + 2 mm"
equation "d126 = LogDia / 2 + 2 mm"
equation "d127 = MateWidth"
equation "d128 = LogDia / 2 + 2 mm"
equation "d129 = LogDia + 1 mm"
equation "d130 = L3_Length"
equation "d132 = L3_FirstNotch - NotchWidth / 2"
equation "d133 = LogDia / 2 - NotchDepth"
equation "d134 = L3_FirstNotch + NotchWidth / 2"
equation "d135 = LogDia / 2 + 2 mm"
equation "d136 = L3_FirstNotch - NotchWidth / 2"
equation "d137 = LogDia / 2 - NotchDepth"
equation "d138 = L3_FirstNotch + NotchWidth / 2"
equation "d139 = LogDia / 2 + 2 mm"
equation "d140 = LogDia + 2 mm"
equation "d142 = max(L3_Notches; 2)"
equation "d144 = L3_NotchStep"
equation "L4_Length = 10.625 in" comment "Overall length"
equation "L4_Notches = 4" comment "Number of notch positions"
equation "L4_FirstNotch = ( L4_Length - ( L4_Notches - 1 ) * NotchCenters ) / 2" comment "Centre of the first notch (keeps the row of notches centred)"
equation "L4_NotchStep = NotchCenters * min(1; L4_Notches - 1) + 0.001 mm * ( 1 - min(1; L4_Notches - 1) )" comment "Pattern step: NotchCenters, or about zero when there is only one notch"
equation "d150 = LogDia / 2"
equation "d151 = PrintFlat / 2"
equation "d152 = LogDia / 2"
equation "d153 = LogDia / 2 - PrintFlat / 2 + LogDia / 2"
equation "d154 = L4_Length"
equation "d156 = LogDia * ( 1 - sqrt(2) / 2 )"
equation "d157 = LogDia / 2 + 2 mm"
equation "d158 = PrintFlat"
equation "d159 = LogDia / 2 + 2 mm"
equation "d160 = LogDia / 2 + 2 mm"
equation "d161 = MateWidth"
equation "d162 = LogDia / 2 + 2 mm"
equation "d163 = LogDia + 1 mm"
equation "d164 = L4_Length"
equation "d166 = L4_FirstNotch - NotchWidth / 2"
equation "d167 = LogDia / 2 - NotchDepth"
equation "d168 = L4_FirstNotch + NotchWidth / 2"
equation "d169 = LogDia / 2 + 2 mm"
equation "d170 = L4_FirstNotch - NotchWidth / 2"
equation "d171 = LogDia / 2 - NotchDepth"
equation "d172 = L4_FirstNotch + NotchWidth / 2"
equation "d173 = LogDia / 2 + 2 mm"
equation "d174 = LogDia + 2 mm"
equation "d176 = max(L4_Notches; 2)"
equation "d178 = L4_NotchStep"
equation "Half2_Length = 4.5 in" comment "Overall length"
equation "Half2_Notches = 2" comment "Number of notch positions"
equation "Half2_FirstNotch = ( Half2_Length - ( Half2_Notches - 1 ) * NotchCenters ) / 2" comment "Centre of the first notch (keeps the row of notches centred)"
equation "Half2_NotchStep = NotchCenters * min(1; Half2_Notches - 1) + 0.001 mm * ( 1 - min(1; Half2_Notches - 1) )" comment "Pattern step: NotchCenters, or about zero when there is only one notch"
equation "d184 = LogDia / 2"
equation "d185 = LogDia / 2"
equation "d186 = LogDia / 2"
equation "d187 = 0 mm + LogDia / 2"
equation "d188 = Half2_Length"
equation "d190 = LogDia * ( 1 - sqrt(2) / 2 )"
equation "d191 = LogDia / 2 + 2 mm"
equation "d192 = LogDia / 2 + 1 mm"
equation "d193 = LogDia / 2 + 2 mm"
equation "d194 = MateWidth / 2"
equation "d196 = LogDia / 2 + 2 mm"
equation "d197 = LogDia + 1 mm"
equation "d198 = MateWidth / 2"
equation "d200 = LogDia / 2 + 2 mm"
equation "d201 = LogDia + 1 mm"
equation "d202 = Half2_Length"
equation "d204 = Half2_FirstNotch - NotchWidth / 2"
equation "d205 = BaseLogHeight - NotchDepth"
equation "d206 = Half2_FirstNotch + NotchWidth / 2"
equation "d207 = BaseLogHeight + 1 mm"
equation "d208 = LogDia + 2 mm"
equation "d210 = max(Half2_Notches; 2)"
equation "d212 = Half2_NotchStep"
equation "Half3_Length = 7.5 in" comment "Overall length"
equation "Half3_Notches = 3" comment "Number of notch positions"
equation "Half3_FirstNotch = ( Half3_Length - ( Half3_Notches - 1 ) * NotchCenters ) / 2" comment "Centre of the first notch (keeps the row of notches centred)"
equation "Half3_NotchStep = NotchCenters * min(1; Half3_Notches - 1) + 0.001 mm * ( 1 - min(1; Half3_Notches - 1) )" comment "Pattern step: NotchCenters, or about zero when there is only one notch"
equation "d218 = LogDia / 2"
equation "d219 = LogDia / 2"
equation "d220 = LogDia / 2"
equation "d221 = 0 mm + LogDia / 2"
equation "d222 = Half3_Length"
equation "d224 = LogDia * ( 1 - sqrt(2) / 2 )"
equation "d225 = LogDia / 2 + 2 mm"
equation "d226 = LogDia / 2 + 1 mm"
equation "d227 = LogDia / 2 + 2 mm"
equation "d228 = MateWidth / 2"
equation "d230 = LogDia / 2 + 2 mm"
equation "d231 = LogDia + 1 mm"
equation "d232 = MateWidth / 2"
equation "d234 = LogDia / 2 + 2 mm"
equation "d235 = LogDia + 1 mm"
equation "d236 = Half3_Length"
equation "d238 = Half3_FirstNotch - NotchWidth / 2"
equation "d239 = BaseLogHeight - NotchDepth"
equation "d240 = Half3_FirstNotch + NotchWidth / 2"
equation "d241 = BaseLogHeight + 1 mm"
equation "d242 = LogDia + 2 mm"
equation "d244 = max(Half3_Notches; 2)"
equation "d246 = Half3_NotchStep"
equation "Bev_Length = 1.5 in" comment "Length along the long edge"
equation "Bev_Angle = 39 deg" comment "Angle of the slanted end (roof pitch of the wooden triangle)"
equation "d250 = LogDia / 2"
equation "d251 = PrintFlat / 2"
equation "d252 = LogDia / 2"
equation "d253 = LogDia / 2 - PrintFlat / 2 + LogDia / 2"
equation "d254 = Bev_Length"
equation "d256 = LogDia * ( 1 - sqrt(2) / 2 )"
equation "d257 = LogDia / 2 + 2 mm"
equation "d258 = PrintFlat"
equation "d259 = LogDia / 2 + 2 mm"
equation "d260 = LogDia / 2 + 2 mm"
equation "d261 = MateWidth"
equation "d262 = LogDia / 2 + 2 mm"
equation "d263 = LogDia + 1 mm"
equation "d264 = Bev_Length"
equation "d266 = Bev_Length"
equation "d267 = LogDia / 2"
equation "d268 = LogDia / 2"
equation "d269 = Bev_Length - LogDia / tan(Bev_Angle)"
equation "d270 = LogDia + 2 mm"
equation "Solid1_Length = 1.375 in" comment "Length"
equation "d273 = LogDia"
equation "d274 = LogDia"
equation "d275 = Solid1_Length"
equation "d277 = LogDia * ( 1 - sqrt(2) / 2 )"
equation "Solid2_Length = 1.625 in" comment "Length"
equation "d279 = LogDia"
equation "d280 = LogDia"
equation "d281 = Solid2_Length"
equation "d283 = LogDia * ( 1 - sqrt(2) / 2 )"
named bodies: "log_1insert_1-5_8_oct", "log_1insert_1-1_2_oct", "log_2insert_4-1_2_oct", "log_3insert_7-5_8_oct", "log_4insert_10-5_8_oct", "base_log_4-1_2_oct", "base_log_7-1_2_oct", "beveled_end_1-1_2_oct", "solid_log_1-3_8_oct", "solid_log_1-5_8_oct"
